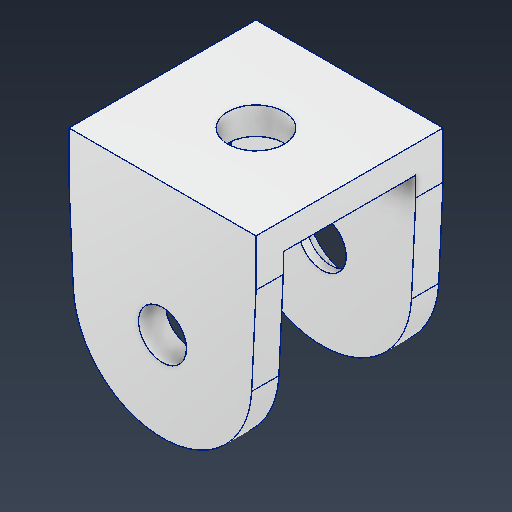
# Autodesk Inventor part: CYLINDER FIXING PARTS_A PARTS
Saved by Autodesk Inventor 2026.2 (Build 302298010, 298A)
## iProperties
Created: 2026-05-13
Part Number: CYLINDER FIXING PARTS_A PARTS
Material: 알루미늄 6061
Document SubType Name: Modeling
Designer: khw
Density: 2.7 g/cm^3
Appearance: 알루미늄 - 평지
Mass: 8.09816 g
Surface Area: 26.4897 cm^2
Volume: 2.99932 cm^3
Author: khw
Autodesk Inventor part; units mm, degrees
ref_plane "YZ Plane" through (0, 0, 0) normal (1, 0, 0) x (0, 1, 0)
ref_plane "XZ Plane" through (0, 0, 0) normal (0, 1, 0) x (-1, 0, 0)
ref_plane "XY Plane" through (0, 0, 0) normal (0, 0, 1) x (1, 0, 0)
sketch "스케치1" plane through (0, 0, 0) normal (0, 0, 1) x (1, 0, 0)
  circle A0 centre (0, 0) radius 2.55
  line L0 (0, 0) -> (0, 14.1)
  line L1 (-9.95, 14.1) -> (9.95, 14.1)
  circle A1 centre (0, 0) radius 9.5
  line L2 (-9.95, 14.1) -> (-9.95, 9.1)
  line L3 (9.95, 14.1) -> (9.95, 9.1)
  line L4 (9.95, 9.1) -> (9.489, -0.4577)
  line L5 (-9.95, 9.1) -> (-9.489, -0.4577)
  dimension "d0" = 5.1
  dimension "d1" = 14.1
  dimension "d2" = 19.9
  dimension "d3" = 23.6
  dimension "d16" = 5
  dimension "d17" = 5
  constraints: 12 end point, 3 vertical, 2 centre point, 2 coincident, 2 point on circle, 2 tangent, 1 horizontal, 1 midpoint
  measures "d0" diameter of A0
  measures "d1" distance of L0.start L0.end
  measures "d2" distance of L1.start L1.end
  measures "d16" distance of L1.start L2.end
  measures "d17" distance of L1.end L3.end
extrude "돌출1" add sketch "스케치1" along normal blind 19.9
sketch "스케치2" plane through (0, 0, 0) normal (1, 0, 0) x (0, 1, 0)
  line L0 (14.1, 0) -> (-0.2999, 0) projected
  line L1 (-0.2999, 0) -> (-0.2999, 19.9) projected
  line L2 (14.1, 19.9) -> (-0.2999, 19.9) projected
  line L3 (14.1, 0) -> (14.1, 19.9) projected
  line L4 (-0.4577, 0) -> (-0.4577, 0) projected
  line L5 (-0.4577, 19.9) -> (-0.4577, 19.9) projected
  line L6 (-0.4577, 0) -> (-0.4577, 19.9) projected
  line L7 (14.1, 9.95) -> (-13.3859, 9.95) construction
  line L8 (11.2, 17) -> (-13.3859, 17)
  line L9 (-13.3859, 17) -> (-13.3859, 2.9)
  line L10 (-13.3859, 2.9) -> (11.2, 2.9)
  line L11 (11.2, 2.9) -> (11.2, 17)
  line L12 (-0.4577, 19.9) -> (-0.4577, 19.9) projected
  line L13 (-2.55, 19.9) -> (2.55, 19.9) projected
  line L14 (14.1, 19.9) -> (9.1, 19.9) projected
  line L15 (9.1, 19.9) -> (-0.4577, 19.9) projected
  line L16 (-0.4577, 19.9) -> (9.1, 19.9) projected
  line L17 (9.1, 19.9) -> (14.1, 19.9) projected
  line L18 (-0.4577, 0) -> (-0.4577, 19.9) projected
  point P0 (0, 0)
  point P1 (11.2, 9.95)
  dimension "d6" = 14.1
  dimension "d7" = 2.9
  constraints: 10 end point, 3 midpoint, 2 horizontal, 2 parallel, 1 perpendicular, 1 point on line
  measures "d6" distance of L9.end L8.end
  measures "d7" distance between parallel lines of L3 L11
extrude "돌출2" cut sketch "스케치2" along normal through all both and the other way through all contours L10 L6 L8 L1 | L1 L8 L11 L10 | L10 L9 L8 L6
sketch "스케치3" plane through (-9.95, 14.1, 0) normal (0, 1, 0) x (1, 0, 0)
  line L0 (19.9, 0) -> (0, 0) projected
  line L1 (0, 0) -> (0, -19.9) projected
  line L2 (19.9, -19.9) -> (0, -19.9) projected
  line L3 (19.9, 0) -> (19.9, -19.9) projected
  line L4 (0, -9.95) -> (19.9, -9.95) construction
  circle A0 centre (9.95, -9.95) radius 3
  point P0 (9.95, 0)
  dimension "d10" = 6
  constraints: 3 midpoint, 2 end point, 1 centre point
  measures "d10" diameter of A0
extrude "돌출3" cut sketch "스케치3" against normal through all contours A0
chamfer "모따기1" distance 2 angle 45 1 edges at (-2.55, 0, 0)
